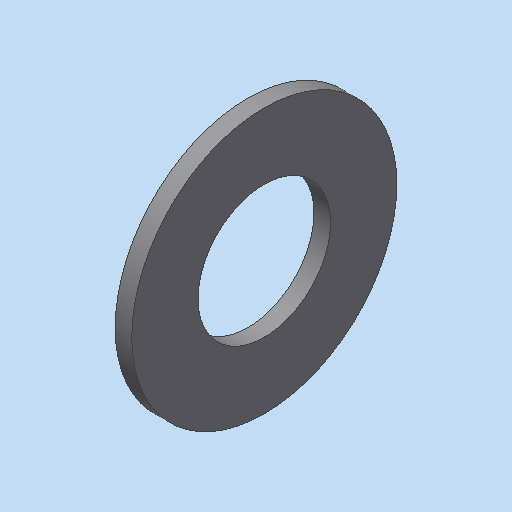
# Autodesk Inventor part: Passscheibe_DIN_988___4x8x0_5
Saved by Autodesk Inventor 2023.3 (Build 273359000, 359)
## iProperties
Shininess: 64.0
Length Units: 11269
Angle Units: 11279
Time Units: 11290
Mass Units: 11283
Length Display Precision: 3
Angle Display Precision: 2
Compacted: True
Part Number: Passscheibe_DIN_988___4x8x0_5
Document SubType Name: Modeling
Created: 2004-04-25
Description: =<RBPARTNOTITLE2>
Vendor: NORM8
Designer: C.Fischer
Manufacturer: Standard
Standards Organization: Custom
Density: 7.85 g/cm^3
Material: xStahl_AnP_Dummymaterial
Appearance: RGB(178,178,178)
Mass: 0.147969 g
Surface Area: 0.942478 cm^2
Volume: 0.0188496 cm^3
Density: 0.0
Volumn: 0.0
Area: 0.0
PropertySet Name: Model Information
Control State: 0
Master: False
Checked Out: False
CNS_NB: Passscheibe DIN 988 - 4x8x0.5
CNS_NN: DIN 988 Passscheiben
CNS_NT: Passscheiben
CNS_NBSYN: Passscheibe DIN 988 - $NENN.
CNS_LINA: Passscheibe DIN 988 - 4x8x0.5
CNS_NENN: 4x8x0.5
CNS_D: 4.000
CNS_DA: 4.000
CNS_DW: 8.000
CNS_H: 0.500
CNS_KT: X
PSOL_IDENT_0: {C:\partsolutions\data\23d-libs\bosch_bamberg\zubehoer\scheiben\din_988_passscheiben.prj},162 {VTYP=
PSOL_IDENT_1: 3D},{NB=Passscheibe DIN 988 - 4x8x0.5},{NN=DIN 988 Passscheiben},{DATE=26.11.2003},{GEOMDATE=26.11.2
PSOL_IDENT_2: 003},{VERSION=v1},{LINEID=130},{LINESUBID=-1},{WBVAR=}  {NB=Passscheibe DIN 988 - 4x8x0.5},{LINA=Pas
PSOL_IDENT_3: sscheibe DIN 988 - 4x8x0.5},{KT=X},{IDNR=},{NENN=4x8x0.5},{D=4.000},{DA=4.000},{DW=8.000},{H=0.500}
RBPARTNOTITLE2: Passscheibe
RBPARTMADEOF: DIN 988 - 4x8x0.5
Title: Passscheibe DIN 988 - 4x8x0.5
Author: C.Fischer
Keywords: =<RBPARTMADEOF>
Revision Number: 01
Autodesk Inventor part; units mm, degrees
sketch "Sketch_1" plane through (0, 0, 0) normal (0, 0, 1) x (1, 0, 0)
  line L0 (0.5, 0) -> (-1, 0)
  line L1 (0, 4) -> (0, 2)
  line L2 (0, 2) -> (0.5, 2)
  line L3 (0.5, 2) -> (0.5, 4)
  line L4 (0.5, 4) -> (0, 4)
  constraints: 10 end point
revolve "Revolution1" add sketch "Sketch_1" angle 360 about axis through (0.5, 0, 0) along (-1, 0, 0)
ref_plane "IP1_XY" through (0, 0, 0) normal (1, 0, 0) x (0, 0, -1)
ref_plane "IP1_YZ" through (0, 0, 0) normal (0, 0, -1) x (0, 1, 0)
ref_plane "IP2_XY" through (0.5, 0, 0) normal (1, 0, 0) x (0, 0, -1)
ref_plane "IP2_YZ" through (0.5, 0, 0) normal (0, 0, -1) x (0, 1, 0)
